Autodesk Fusion 360 part; units mm, degrees
(part 2 of 2)
ref_plane "WorkPlane125" through (0, 0, 11) normal (0, 0, 1) x (1, 0, 0)
sketch "magnet_N_st4_a3_d0" plane through (0, 0, 11) normal (0, 0, 1) x (1, 0, 0)
  line L0 (80.2, 10) -> (99.8, 10)
  line L1 (99.8, 10) -> (99.8, 20)
  line L2 (99.8, 20) -> (80.2, 20)
  line L3 (80.2, 20) -> (80.2, 10)
extrude "Extrude85" add sketch "magnet_N_st4_a3_d0" along normal mid plane 5 separate body makes body 105
ref_plane "WorkPlane126" through (0, 0, 16) normal (0, 0, 1) x (1, 0, 0)
sketch "magnet_N_st4_a3_d1" plane through (0, 0, 16) normal (0, 0, 1) x (1, 0, 0)
  line L0 (80.2, 10) -> (99.8, 10)
  line L1 (99.8, 10) -> (99.8, 20)
  line L2 (99.8, 20) -> (80.2, 20)
  line L3 (80.2, 20) -> (80.2, 10)
extrude "Extrude86" add sketch "magnet_N_st4_a3_d1" along normal mid plane 5 separate body makes body 106
ref_plane "WorkPlane127" through (0, 0, -11) normal (0, 0, 1) x (1, 0, 0)
sketch "magnet_S_st4_a3_d0" plane through (0, 0, -11) normal (0, 0, 1) x (1, 0, 0)
  line L0 (80.2, 10) -> (99.8, 10)
  line L1 (99.8, 10) -> (99.8, 20)
  line L2 (99.8, 20) -> (80.2, 20)
  line L3 (80.2, 20) -> (80.2, 10)
extrude "Extrude87" add sketch "magnet_S_st4_a3_d0" along normal mid plane 5 separate body makes body 107
ref_plane "WorkPlane128" through (0, 0, -16) normal (0, 0, 1) x (1, 0, 0)
sketch "magnet_S_st4_a3_d1" plane through (0, 0, -16) normal (0, 0, 1) x (1, 0, 0)
  line L0 (80.2, 10) -> (99.8, 10)
  line L1 (99.8, 10) -> (99.8, 20)
  line L2 (99.8, 20) -> (80.2, 20)
  line L3 (80.2, 20) -> (80.2, 10)
extrude "Extrude88" add sketch "magnet_S_st4_a3_d1" along normal mid plane 5 separate body makes body 108
ref_plane "WorkPlane129" through (0, 0, 11) normal (0, 0, 1) x (1, 0, 0)
sketch "magnet_N_st5_a0_d0" plane through (0, 0, 11) normal (0, 0, 1) x (1, 0, 0)
  line L0 (100.2, -20) -> (119.8, -20)
  line L1 (119.8, -20) -> (119.8, -10)
  line L2 (119.8, -10) -> (100.2, -10)
  line L3 (100.2, -10) -> (100.2, -20)
extrude "Extrude89" add sketch "magnet_N_st5_a0_d0" along normal mid plane 5 separate body makes body 109
ref_plane "WorkPlane130" through (0, 0, 16) normal (0, 0, 1) x (1, 0, 0)
sketch "magnet_N_st5_a0_d1" plane through (0, 0, 16) normal (0, 0, 1) x (1, 0, 0)
  line L0 (100.2, -20) -> (119.8, -20)
  line L1 (119.8, -20) -> (119.8, -10)
  line L2 (119.8, -10) -> (100.2, -10)
  line L3 (100.2, -10) -> (100.2, -20)
extrude "Extrude90" add sketch "magnet_N_st5_a0_d1" along normal mid plane 5 separate body makes body 110
ref_plane "WorkPlane131" through (0, 0, -11) normal (0, 0, 1) x (1, 0, 0)
sketch "magnet_S_st5_a0_d0" plane through (0, 0, -11) normal (0, 0, 1) x (1, 0, 0)
  line L0 (100.2, -20) -> (119.8, -20)
  line L1 (119.8, -20) -> (119.8, -10)
  line L2 (119.8, -10) -> (100.2, -10)
  line L3 (100.2, -10) -> (100.2, -20)
extrude "Extrude91" add sketch "magnet_S_st5_a0_d0" along normal mid plane 5 separate body makes body 111
ref_plane "WorkPlane132" through (0, 0, -16) normal (0, 0, 1) x (1, 0, 0)
sketch "magnet_S_st5_a0_d1" plane through (0, 0, -16) normal (0, 0, 1) x (1, 0, 0)
  line L0 (100.2, -20) -> (119.8, -20)
  line L1 (119.8, -20) -> (119.8, -10)
  line L2 (119.8, -10) -> (100.2, -10)
  line L3 (100.2, -10) -> (100.2, -20)
extrude "Extrude92" add sketch "magnet_S_st5_a0_d1" along normal mid plane 5 separate body makes body 112
ref_plane "WorkPlane133" through (0, 0, 11) normal (0, 0, 1) x (1, 0, 0)
sketch "magnet_N_st5_a1_d0" plane through (0, 0, 11) normal (0, 0, 1) x (1, 0, 0)
  line L0 (100.2, -10) -> (119.8, -10)
  line L1 (119.8, -10) -> (119.8, 0)
  line L2 (119.8, 0) -> (100.2, 0)
  line L3 (100.2, 0) -> (100.2, -10)
extrude "Extrude93" add sketch "magnet_N_st5_a1_d0" along normal mid plane 5 separate body makes body 113
ref_plane "WorkPlane134" through (0, 0, 16) normal (0, 0, 1) x (1, 0, 0)
sketch "magnet_N_st5_a1_d1" plane through (0, 0, 16) normal (0, 0, 1) x (1, 0, 0)
  line L0 (100.2, -10) -> (119.8, -10)
  line L1 (119.8, -10) -> (119.8, 0)
  line L2 (119.8, 0) -> (100.2, 0)
  line L3 (100.2, 0) -> (100.2, -10)
extrude "Extrude94" add sketch "magnet_N_st5_a1_d1" along normal mid plane 5 separate body makes body 114
ref_plane "WorkPlane135" through (0, 0, -11) normal (0, 0, 1) x (1, 0, 0)
sketch "magnet_S_st5_a1_d0" plane through (0, 0, -11) normal (0, 0, 1) x (1, 0, 0)
  line L0 (100.2, -10) -> (119.8, -10)
  line L1 (119.8, -10) -> (119.8, 0)
  line L2 (119.8, 0) -> (100.2, 0)
  line L3 (100.2, 0) -> (100.2, -10)
extrude "Extrude95" add sketch "magnet_S_st5_a1_d0" along normal mid plane 5 separate body makes body 115
ref_plane "WorkPlane136" through (0, 0, -16) normal (0, 0, 1) x (1, 0, 0)
sketch "magnet_S_st5_a1_d1" plane through (0, 0, -16) normal (0, 0, 1) x (1, 0, 0)
  line L0 (100.2, -10) -> (119.8, -10)
  line L1 (119.8, -10) -> (119.8, 0)
  line L2 (119.8, 0) -> (100.2, 0)
  line L3 (100.2, 0) -> (100.2, -10)
extrude "Extrude96" add sketch "magnet_S_st5_a1_d1" along normal mid plane 5 separate body makes body 116
ref_plane "WorkPlane137" through (0, 0, 11) normal (0, 0, 1) x (1, 0, 0)
sketch "magnet_N_st5_a2_d0" plane through (0, 0, 11) normal (0, 0, 1) x (1, 0, 0)
  line L0 (100.2, 0) -> (119.8, 0)
  line L1 (119.8, 0) -> (119.8, 10)
  line L2 (119.8, 10) -> (100.2, 10)
  line L3 (100.2, 10) -> (100.2, 0)
extrude "Extrude97" add sketch "magnet_N_st5_a2_d0" along normal mid plane 5 separate body makes body 117
ref_plane "WorkPlane138" through (0, 0, 16) normal (0, 0, 1) x (1, 0, 0)
sketch "magnet_N_st5_a2_d1" plane through (0, 0, 16) normal (0, 0, 1) x (1, 0, 0)
  line L0 (100.2, 0) -> (119.8, 0)
  line L1 (119.8, 0) -> (119.8, 10)
  line L2 (119.8, 10) -> (100.2, 10)
  line L3 (100.2, 10) -> (100.2, 0)
extrude "Extrude98" add sketch "magnet_N_st5_a2_d1" along normal mid plane 5 separate body makes body 118
ref_plane "WorkPlane139" through (0, 0, -11) normal (0, 0, 1) x (1, 0, 0)
sketch "magnet_S_st5_a2_d0" plane through (0, 0, -11) normal (0, 0, 1) x (1, 0, 0)
  line L0 (100.2, 0) -> (119.8, 0)
  line L1 (119.8, 0) -> (119.8, 10)
  line L2 (119.8, 10) -> (100.2, 10)
  line L3 (100.2, 10) -> (100.2, 0)
extrude "Extrude99" add sketch "magnet_S_st5_a2_d0" along normal mid plane 5 separate body makes body 119
ref_plane "WorkPlane140" through (0, 0, -16) normal (0, 0, 1) x (1, 0, 0)
sketch "magnet_S_st5_a2_d1" plane through (0, 0, -16) normal (0, 0, 1) x (1, 0, 0)
  line L0 (100.2, 0) -> (119.8, 0)
  line L1 (119.8, 0) -> (119.8, 10)
  line L2 (119.8, 10) -> (100.2, 10)
  line L3 (100.2, 10) -> (100.2, 0)
extrude "Extrude100" add sketch "magnet_S_st5_a2_d1" along normal mid plane 5 separate body makes body 120
ref_plane "WorkPlane141" through (0, 0, 11) normal (0, 0, 1) x (1, 0, 0)
sketch "magnet_N_st5_a3_d0" plane through (0, 0, 11) normal (0, 0, 1) x (1, 0, 0)
  line L0 (100.2, 10) -> (119.8, 10)
  line L1 (119.8, 10) -> (119.8, 20)
  line L2 (119.8, 20) -> (100.2, 20)
  line L3 (100.2, 20) -> (100.2, 10)
extrude "Extrude101" add sketch "magnet_N_st5_a3_d0" along normal mid plane 5 separate body makes body 121
ref_plane "WorkPlane142" through (0, 0, 16) normal (0, 0, 1) x (1, 0, 0)
sketch "magnet_N_st5_a3_d1" plane through (0, 0, 16) normal (0, 0, 1) x (1, 0, 0)
  line L0 (100.2, 10) -> (119.8, 10)
  line L1 (119.8, 10) -> (119.8, 20)
  line L2 (119.8, 20) -> (100.2, 20)
  line L3 (100.2, 20) -> (100.2, 10)
extrude "Extrude102" add sketch "magnet_N_st5_a3_d1" along normal mid plane 5 separate body makes body 122
ref_plane "WorkPlane143" through (0, 0, -11) normal (0, 0, 1) x (1, 0, 0)
sketch "magnet_S_st5_a3_d0" plane through (0, 0, -11) normal (0, 0, 1) x (1, 0, 0)
  line L0 (100.2, 10) -> (119.8, 10)
  line L1 (119.8, 10) -> (119.8, 20)
  line L2 (119.8, 20) -> (100.2, 20)
  line L3 (100.2, 20) -> (100.2, 10)
extrude "Extrude103" add sketch "magnet_S_st5_a3_d0" along normal mid plane 5 separate body makes body 123
ref_plane "WorkPlane144" through (0, 0, -16) normal (0, 0, 1) x (1, 0, 0)
sketch "magnet_S_st5_a3_d1" plane through (0, 0, -16) normal (0, 0, 1) x (1, 0, 0)
  line L0 (100.2, 10) -> (119.8, 10)
  line L1 (119.8, 10) -> (119.8, 20)
  line L2 (119.8, 20) -> (100.2, 20)
  line L3 (100.2, 20) -> (100.2, 10)
extrude "Extrude104" add sketch "magnet_S_st5_a3_d1" along normal mid plane 5 separate body makes body 124
ref_plane "WorkPlane145" through (0, 0, 19.5) normal (0, 0, 1) x (1, 0, 0)
sketch "hood_top" plane through (0, 0, 19.5) normal (0, 0, 1) x (1, 0, 0)
  line L0 (-1, -26) -> (121, -26)
  line L1 (121, -26) -> (121, 26)
  line L2 (121, 26) -> (-1, 26)
  line L3 (-1, 26) -> (-1, -26)
extrude "Extrude105" add sketch "hood_top" along normal mid plane 2 separate body makes body 125
ref_plane "WorkPlane146" through (0, 0, -19.5) normal (0, 0, 1) x (1, 0, 0)
sketch "hood_bottom" plane through (0, 0, -19.5) normal (0, 0, 1) x (1, 0, 0)
  line L0 (-1, -26) -> (121, -26)
  line L1 (121, -26) -> (121, 26)
  line L2 (121, 26) -> (-1, 26)
  line L3 (-1, 26) -> (-1, -26)
extrude "Extrude106" add sketch "hood_bottom" along normal mid plane 2 separate body makes body 126
ref_plane "WorkPlane147" through (0, 24.5, 0) normal (0, 1, 0) x (0, 0, 1)
sketch "endbar_rear_p" plane through (0, 24.5, 0) normal (0, 1, 0) x (1, 0, 0)
  line L0 (118, -18.5) -> (120, -18.5)
  line L1 (120, -18.5) -> (120, 18.5)
  line L2 (120, 18.5) -> (118, 18.5)
  line L3 (118, 18.5) -> (118, -18.5)
extrude "Extrude107" add sketch "endbar_rear_p" along normal mid plane 2 separate body makes body 127
ref_plane "WorkPlane148" through (0, -24.5, 0) normal (0, 1, 0) x (0, 0, 1)
sketch "endbar_rear_n" plane through (0, -24.5, 0) normal (0, 1, 0) x (1, 0, 0)
  line L0 (118, -18.5) -> (120, -18.5)
  line L1 (120, -18.5) -> (120, 18.5)
  line L2 (120, 18.5) -> (118, 18.5)
  line L3 (118, 18.5) -> (118, -18.5)
extrude "Extrude108" add sketch "endbar_rear_n" along normal mid plane 2 separate body makes body 128
named bodies: "plate_a", "plate_b", "rail_left", "rail_right", "bm_top_s00", "bm_top_s01", "bm_top_s02", "bm_top_s03", "bm_top_s04", "bm_bottom_s00", "bm_bottom_s01", "bm_bottom_s02", "bm_bottom_s03", "bm_bottom_s04", "bm_left_s00", "bm_left_s01", "bm_left_s02", "bm_left_s03", "bm_left_s04", "bm_right_s00", "bm_right_s01", "bm_right_s02", "bm_right_s03", "bm_right_s04", "front_flange", "rear_cap", "graphite_left", "graphite_right", "magnet_N_st0_a0_d0", "magnet_N_st0_a0_d1", "magnet_S_st0_a0_d0", "magnet_S_st0_a0_d1", "magnet_N_st0_a1_d0", "magnet_N_st0_a1_d1", "magnet_S_st0_a1_d0", "magnet_S_st0_a1_d1", "magnet_N_st0_a2_d0", "magnet_N_st0_a2_d1", "magnet_S_st0_a2_d0", "magnet_S_st0_a2_d1", "magnet_N_st0_a3_d0", "magnet_N_st0_a3_d1", "magnet_S_st0_a3_d0", "magnet_S_st0_a3_d1", "magnet_N_st1_a0_d0", "magnet_N_st1_a0_d1", "magnet_S_st1_a0_d0", "magnet_S_st1_a0_d1", "magnet_N_st1_a1_d0", "magnet_N_st1_a1_d1", "magnet_S_st1_a1_d0", "magnet_S_st1_a1_d1", "magnet_N_st1_a2_d0", "magnet_N_st1_a2_d1", "magnet_S_st1_a2_d0", "magnet_S_st1_a2_d1", "magnet_N_st1_a3_d0", "magnet_N_st1_a3_d1", "magnet_S_st1_a3_d0", "magnet_S_st1_a3_d1", "magnet_N_st2_a0_d0", "magnet_N_st2_a0_d1", "magnet_S_st2_a0_d0", "magnet_S_st2_a0_d1", "magnet_N_st2_a1_d0", "magnet_N_st2_a1_d1", "magnet_S_st2_a1_d0", "magnet_S_st2_a1_d1", "magnet_N_st2_a2_d0", "magnet_N_st2_a2_d1", "magnet_S_st2_a2_d0", "magnet_S_st2_a2_d1", "magnet_N_st2_a3_d0", "magnet_N_st2_a3_d1", "magnet_S_st2_a3_d0", "magnet_S_st2_a3_d1", "magnet_N_st3_a0_d0", "magnet_N_st3_a0_d1", "magnet_S_st3_a0_d0", "magnet_S_st3_a0_d1", "magnet_N_st3_a1_d0", "magnet_N_st3_a1_d1", "magnet_S_st3_a1_d0", "magnet_S_st3_a1_d1", "magnet_N_st3_a2_d0", "magnet_N_st3_a2_d1", "magnet_S_st3_a2_d0", "magnet_S_st3_a2_d1", "magnet_N_st3_a3_d0", "magnet_N_st3_a3_d1", "magnet_S_st3_a3_d0", "magnet_S_st3_a3_d1", "magnet_N_st4_a0_d0", "magnet_N_st4_a0_d1", "magnet_S_st4_a0_d0", "magnet_S_st4_a0_d1", "magnet_N_st4_a1_d0", "magnet_N_st4_a1_d1", "magnet_S_st4_a1_d0", "magnet_S_st4_a1_d1", "magnet_N_st4_a2_d0", "magnet_N_st4_a2_d1", "magnet_S_st4_a2_d0", "magnet_S_st4_a2_d1", "magnet_N_st4_a3_d0", "magnet_N_st4_a3_d1", "magnet_S_st4_a3_d0", "magnet_S_st4_a3_d1", "magnet_N_st5_a0_d0", "magnet_N_st5_a0_d1", "magnet_S_st5_a0_d0", "magnet_S_st5_a0_d1", "magnet_N_st5_a1_d0", "magnet_N_st5_a1_d1", "magnet_S_st5_a1_d0", "magnet_S_st5_a1_d1", "magnet_N_st5_a2_d0", "magnet_N_st5_a2_d1", "magnet_S_st5_a2_d0", "magnet_S_st5_a2_d1", "magnet_N_st5_a3_d0", "magnet_N_st5_a3_d1", "magnet_S_st5_a3_d0", "magnet_S_st5_a3_d1", "hood_top", "hood_bottom", "endbar_rear_p", "endbar_rear_n"
